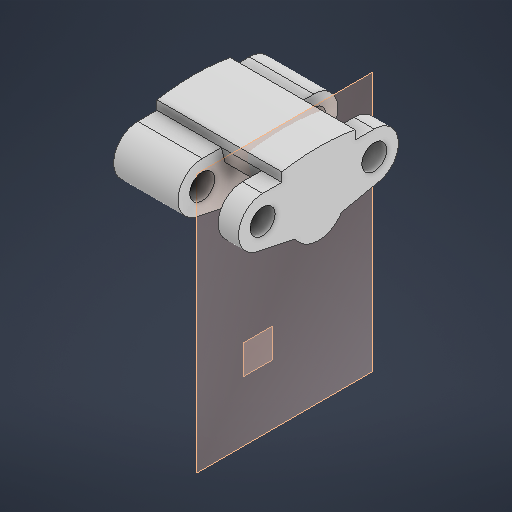
# Autodesk Inventor part: SC1_Rough_CAD
Saved by Autodesk Inventor 2026.1 (Build 301233000, 233)
## iProperties
Created: 2026-10-13
Part Number: SC1_Rough_CAD
Material: Generic
Document SubType Name: Modeling
Designer: share
Density: 1 g/cm^3
Appearance: Default
Author: share
Autodesk Inventor part; units mm, degrees
ref_plane "XZ Plane" through (0, 0, 0) normal (0, 1, 0) x (-1, 0, 0)
ref_plane "XY Plane" through (0, 0, 0) normal (0, 0, 1) x (1, 0, 0)
ref_plane "Work Plane1" through (-18.3, 0, 0) normal (1, 0, 0) x (0, 1, 0)
sketch "Sketch1" plane through (-18.3, 0, 0) normal (1, 0, 0) x (0, 1, 0)
  circle A0 centre (0, 0) radius 141.5 construction
  line L0 (0, 198.1) -> (0, -198.1) construction
  line L1 (-198.1, 0) -> (198.1, 0) construction
  line L2 (116.586, 38.1) -> (116.586, -38.1) construction
  circle A1 centre (116.586, 38.1) radius 8.509
  circle A2 centre (116.586, -38.1) radius 8.509
  circle A3 centre (116.586, 38.1) radius 16.51
  circle A4 centre (116.586, -38.1) radius 16.51
  arc A5 (139.274, -25) -> (139.274, 25) centre (0, 0) ccw
  line L3 (139.274, 25) -> (133.096, 25)
  line L4 (139.274, -25) -> (133.096, -25)
  line L5 (133.096, 38.1) -> (133.096, 25)
  line L6 (133.096, -25) -> (133.096, -38.1)
  circle A6 centre (104.586, 0) radius 18.415
  line L7 (100.4305, 41.5032) -> (95, 15.7233)
  line L8 (100.4305, -41.5032) -> (95, -15.7233)
  line L9 (116.586, 54.61) -> (130.5373, 54.61) construction
  line L10 (116.586, -54.61) -> (130.5373, -54.61) construction
  line L11 (95, 15.7233) -> (95, -15.7233) construction
  dimension "d1" = 283
  dimension "d3" = 76.2
  dimension "d4" = 116.586
  dimension "d5" = 17.018
  dimension "d7" = 50
  dimension "d8" = 12
  dimension "d9" = 36.83
  dimension "d10" = 109.22
  dimension "d15" = 95
  constraints: 20 end point, 14 point on circle, 7 centre point, 6 tangent, 5 coincident, 4 perpendicular, 3 equal radius, 3 vertical, 2 symmetric about line, 1 equal length, 1 horizontal, 1 parallel, 1 point on line
  measures "d1" diameter of A0
  measures "d3" distance of L2.end L2.start
  measures "d4" distance between parallel lines of L0 L2
  measures "d5" diameter of A1
  measures "d7" distance of L4.start L3.start
  measures "d8" distance from line of A6.centre L2
  measures "d9" diameter of A6
  measures "d10" distance between parallel lines of L10 L9
  measures "d15" distance between parallel lines of L0 L11
extrude "Extrusion1" add sketch "Sketch1" along normal blind 41.3 and the other way blind 44
sketch "Sketch2" plane through (0, 0, 0) normal (1, 0, 0) x (0, 1, 0)
  circle A0 centre (0, 0) radius 114.286
  dimension "d16" = 228.572
  constraints: 1 centre point, 1 coincident
  measures "d16" diameter of A0
extrude "Extrusion2" cut sketch "Sketch2" along normal blind 9.15 and the other way blind 18.3
sketch "Sketch3" plane through (0, 0, 0) normal (1, 0, 0) x (0, 1, 0)
  arc A0 (133.096, 38.1) -> (100.4305, 41.5032) centre (116.586, 38.1) ccw projected
  line L0 (100.4305, 41.5032) -> (95, 15.7233) projected
  arc A1 (95, 15.7233) -> (95, -15.7233) centre (104.586, 0) ccw projected
  line L1 (95, -15.7233) -> (100.4305, -41.5032) projected
  arc A2 (100.4305, -41.5032) -> (133.096, -38.1) centre (116.586, -38.1) ccw projected
  line L2 (133.096, -38.1) -> (133.096, -25) projected
  line L3 (133.096, -25) -> (139.274, -25) projected
  arc A3 (139.274, -25) -> (139.274, 25) centre (0, 0) ccw projected
  line L4 (139.274, 25) -> (133.096, 25) projected
  line L5 (133.096, 25) -> (133.096, 38.1) projected
  circle A4 centre (116.586, 38.1) radius 8.509 projected
  circle A5 centre (116.586, -38.1) radius 8.509 projected
  line L6 (133.096, 25) -> (95, 15.7233)
  line L7 (133.096, -25) -> (95, -15.7233)
  line L8 (123.096, 22.5649) -> (123.096, -22.5649)
  point P0 (0, 0)
  dimension "d22" = 10
  constraints: 6 end point, 2 point on line, 1 vertical
  measures "d22" distance between parallel lines of L8 L5
extrude "Extrusion3" cut sketch "Sketch3" along normal blind 9.15 and the other way blind 18.3 contours L5 L6 L0 A0 | L6 L8 L7 A1 | L7 L2 A2 L1 | A4 | A5
body "Solid1"
